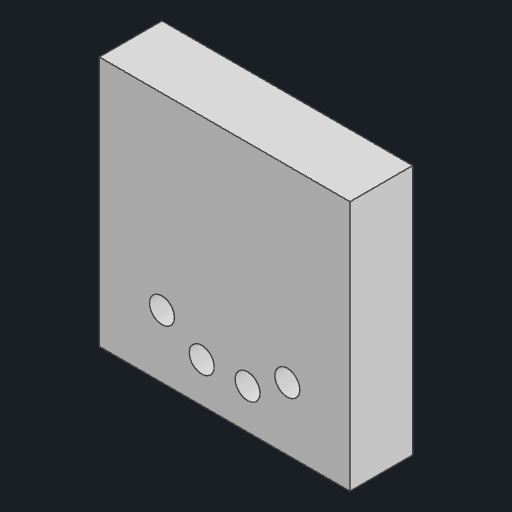
# Autodesk Inventor part: fit90
Saved by Autodesk Inventor 2026.1 (Build 301233000, 233)
## iProperties
Created: 2026-10-30
Part Number: fit90
Material: Generic
Document SubType Name: Modeling
Designer: anony
Density: 1 g/cm^3
Appearance: Default
Author: anony
Autodesk Inventor part; units mm, degrees
ref_plane "YZ Plane" through (0, 0, 0) normal (1, 0, 0) x (0, 1, 0)
ref_plane "XZ Plane" through (0, 0, 0) normal (0, 1, 0) x (-1, 0, 0)
ref_plane "XY Plane" through (0, 0, 0) normal (0, 0, 1) x (1, 0, 0)
sketch "Sketch1" plane through (0, 0, 0) normal (0, 0, 1) x (1, 0, 0)
  line L0 (-20, -20) -> (20, -20)
  line L1 (20, -20) -> (20, 20)
  line L2 (20, 20) -> (-20, 20)
  line L3 (-20, 20) -> (-20, -20)
  constraints: 8 end point, 2 parallel, 1 horizontal, 1 perpendicular
extrude "Extrusion1" add sketch "Sketch1" along normal mid plane 10
sketch "Sketch2" plane through (0, 0, 0) normal (0, 0, 1) x (1, 0, 0)
  circle A0 centre (-10, -10) radius 2
  constraints: 1 centre point
extrude "Extrusion2" cut sketch "Sketch2" along normal through all both and the other way through all
pattern_circular "Circular Pattern1" count 4 over 90 about axis through (0, 0, -10) along (0, 0, 1) of "Extrusion2"
body "Solid1"
